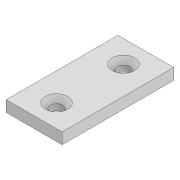
# Autodesk Inventor part: Rotorschutz_SL_BT3
Saved by Autodesk Inventor 2020.1 (Build 241239000, 239)
## iProperties
Created: 2020-09-23
Part Number: Rotorschutz_SL_BT3
Material: Generisch
Document SubType Name: Modeling
Designer: s5chfeis
Density: 1 g/cm^3
Appearance: Vorgabe
Author: s5chfeis
Autodesk Inventor part; units mm, degrees
ref_plane "YZ Plane" through (0, 0, 0) normal (1, 0, 0) x (0, 1, 0)
ref_plane "XZ Plane" through (0, 0, 0) normal (0, 1, 0) x (-1, 0, 0)
ref_plane "XY Plane" through (0, 0, 0) normal (0, 0, 1) x (1, 0, 0)
sketch "Skizze1" plane through (0, 0, 0) normal (0, 1, 0) x (-1, 0, 0)
  line L0 (0, 0) -> (50, 0)
  line L1 (50, 0) -> (50, -100)
  line L2 (50, -100) -> (0, -100)
  line L3 (0, -100) -> (0, 0)
  dimension "d0" = 50
  dimension "d1" = 100
  constraints: 8 end point, 2 parallel, 1 horizontal, 1 perpendicular
  measures "d0" distance of L1.end L2.end
  measures "d1" distance of L0.end L1.end
extrude "Extrusion1" add sketch "Skizze1" along normal blind 10
sketch "Skizze2" plane through (0, 10, 0) normal (0, 1, 0) x (1, 0, 0)
  line L0 (0, 0) -> (0, 20) construction
  line L1 (0, 0) -> (0, 100) construction
  line L2 (0, 0) -> (20, 0) construction
  line L3 (0, 20) -> (-25, 20) construction
  line L4 (0, 100) -> (0, 80) construction
  line L5 (0, 100) -> (20, 100) construction
  line L6 (0, 80) -> (-25, 80) construction
  dimension "d4" = 20
  dimension "d5" = 90
  dimension "d6" = 25
  dimension "d7" = 90
  dimension "d8" = 20
  dimension "d9" = 90
  dimension "d10" = 25
  dimension "d11" = 90
  constraints: 12 end point, 4 perpendicular, 2 coincident, 2 collinear, 2 horizontal
  measures "d4" distance of L0.start L0.end
  measures "d5" angle of L2 L0
  measures "d6" distance of L0.end L3.end
  measures "d7" angle of L3 L0
  measures "d8" distance of L1.end L4.end
  measures "d9" angle of L4 L5
  measures "d10" distance of L4.end L6.end
  measures "d11" angle of L4 L6
hole "Bohrung1" at (-25, 10, -20) at (-25, 10, -80) direction (0, -1, 0) diameter 11 depth 27.3 tip angle 118 countersink diameter 20 countersink angle 90 clearance for "Flachkopfsenkschraube DIN EN ISO 2009" size "M10" standard "DIN"
